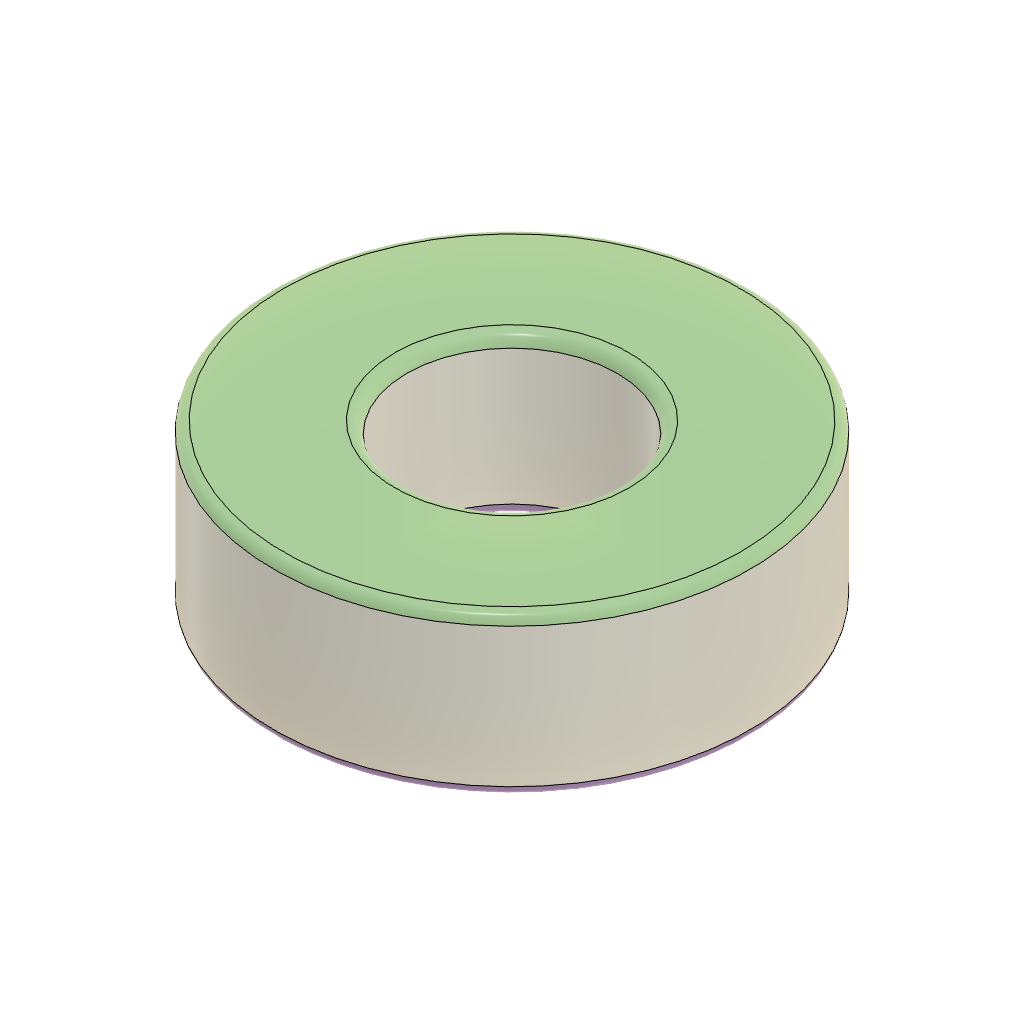
spacer_barrel_fastener (Autodesk Fusion 360 design; units mm, degrees)
part number: 2026-10-03-17-22-58-029
Autodesk Fusion 360 part; units mm, degrees
sketch "Sketch1" plane through (0, 0, 0) normal (0, 0, 1) x (1, 0, 0)
  circle A0 centre (0, 0) radius 2.65
  circle A1 centre (0, 0) radius 6
  dimension "d1" = 5.3
  dimension "d2" = 12
  constraint coincident A0.centre A1.centre
  constraint concentric A0 A1
  measures "d1" diameter of A0
  measures "d2" diameter of A1
extrude "Extrude1" add sketch "Sketch1" along normal blind 4
fillet "Fillet1" radius 0.3 1 edges at (-2.4707, 0.9583, 4)
fillet "Fillet2" radius 0.3 1 edges at (-2.4707, 0.9583, 0)
fillet "Fillet3" radius 0.25 1 edges at (-5.594, -2.1697, 4)
fillet "Fillet4" radius 0.25 1 edges at (-5.594, -2.1697, 0)
